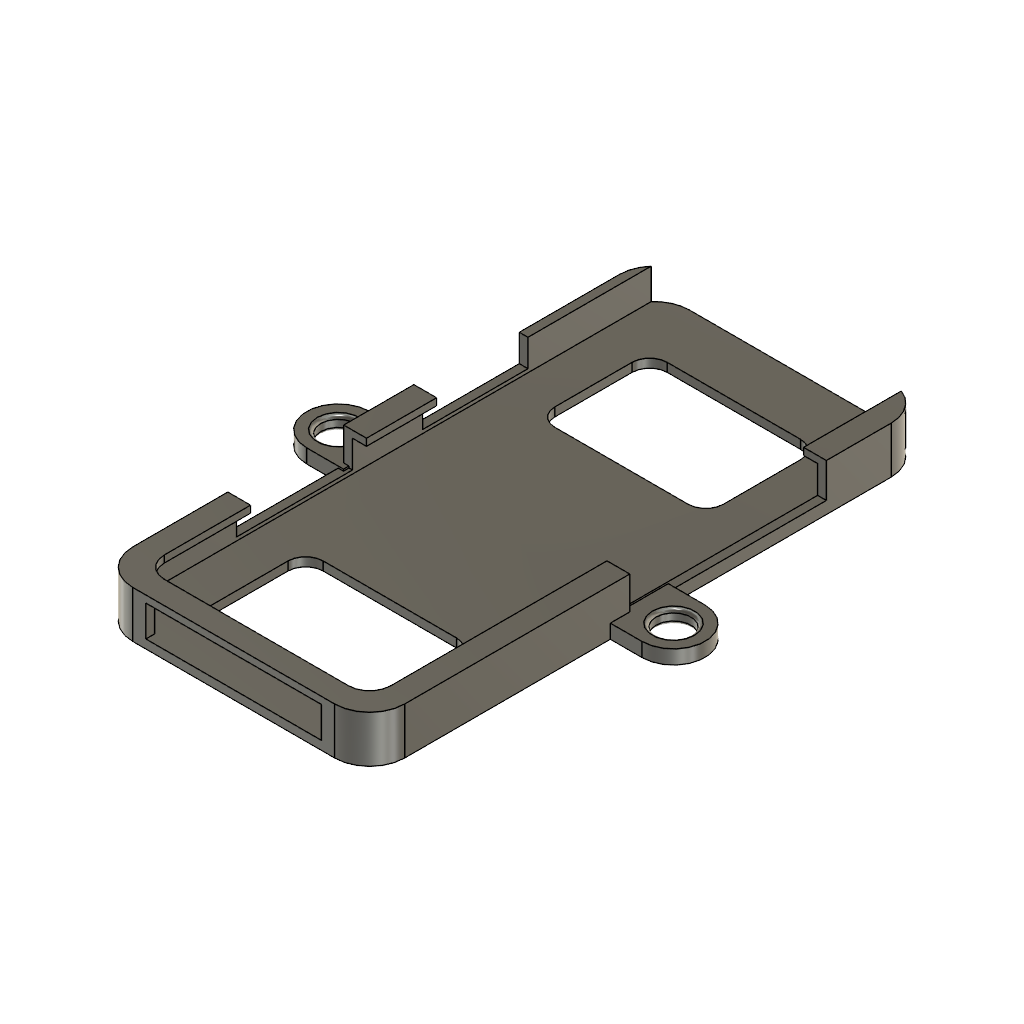
iphone holder 16 pro (Autodesk Fusion 360 design; units mm, degrees)
Autodesk Fusion 360 part; units mm, degrees
sketch "Outer" plane through (0, 0, 0) normal (0, 0, 1) x (1, 0, 0)
  line L0 (-28.75, -2.5) -> (28.75, -2.5)
  line L1 (38.75, 7.5) -> (38.75, 146.1)
  line L2 (28.75, 156.1) -> (-28.75, 156.1)
  line L3 (-38.75, 146.1) -> (-38.75, 7.5)
  arc A0 (28.75, -2.5) -> (38.75, 7.5) centre (28.75, 7.5) ccw
  arc A1 (38.75, 146.1) -> (28.75, 156.1) centre (28.75, 146.1) ccw
  arc A2 (-28.75, 156.1) -> (-38.75, 146.1) centre (-28.75, 146.1) ccw
  arc A3 (-38.75, 7.5) -> (-28.75, -2.5) centre (-28.75, 7.5) ccw
extrude "Shell" add sketch "Outer" along normal blind 13.35
sketch "Pocket" plane through (0, 0, 0) normal (0, 0, 1) x (1, 0, 0)
  line L0 (-28.25, 0) -> (28.25, 0)
  line L1 (36.25, 8) -> (36.25, 168.1)
  line L2 (28.25, 176.1) -> (-28.25, 176.1)
  line L3 (-36.25, 168.1) -> (-36.25, 8)
  arc A0 (28.25, 0) -> (36.25, 8) centre (28.25, 8) ccw
  arc A1 (36.25, 168.1) -> (28.25, 176.1) centre (28.25, 168.1) ccw
  arc A2 (-28.25, 176.1) -> (-36.25, 168.1) centre (-28.25, 168.1) ccw
  arc A3 (-36.25, 8) -> (-28.25, 0) centre (-28.25, 8) ccw
extrude "Pocket (1)" cut sketch "Pocket" along normal blind 8.85 from surface at 2.5
sketch "LipWindow" plane through (0, 0, 0) normal (0, 0, 1) x (1, 0, 0)
  line L0 (-26.25, 4) -> (26.25, 4)
  line L1 (32.25, 10) -> (32.25, 170.1)
  line L2 (26.25, 176.1) -> (-26.25, 176.1)
  line L3 (-32.25, 170.1) -> (-32.25, 10)
  arc A0 (26.25, 4) -> (32.25, 10) centre (26.25, 10) ccw
  arc A1 (32.25, 170.1) -> (26.25, 176.1) centre (26.25, 170.1) ccw
  arc A2 (-26.25, 176.1) -> (-32.25, 170.1) centre (-26.25, 170.1) ccw
  arc A3 (-32.25, 10) -> (-26.25, 4) centre (-26.25, 10) ccw
extrude "LipWindow (1)" cut sketch "LipWindow" along normal blind 3.1 from surface at 11.25
sketch "CameraClear" plane through (0, 0, 0) normal (0, 0, 1) x (1, 0, 0)
  line L0 (-43.75, 94.6) -> (-31.25, 94.6)
  line L1 (-31.25, 94.6) -> (-31.25, 176.1)
  line L2 (-31.25, 176.1) -> (-43.75, 176.1)
  line L3 (-43.75, 176.1) -> (-43.75, 94.6)
extrude "CameraClear (1)" cut sketch "CameraClear" along normal blind 3.1 from surface at 11.25
sketch "BottomPort" plane through (0, 0, 0) normal (0, 0, 1) x (1, 0, 0)
  line L0 (-25, -7.5) -> (25, -7.5)
  line L1 (25, -7.5) -> (25, 1)
  line L2 (25, 1) -> (-25, 1)
  line L3 (-25, 1) -> (-25, -7.5)
extrude "BottomPort (1)" cut sketch "BottomPort" along normal blind 8.85 from surface at 2.5
sketch "VolSlot" plane through (0, 0, 0) normal (0, 0, 1) x (1, 0, 0)
  line L0 (31.25, 71.6) -> (43.75, 71.6)
  line L1 (43.75, 71.6) -> (43.75, 127.6)
  line L2 (43.75, 127.6) -> (31.25, 127.6)
  line L3 (31.25, 127.6) -> (31.25, 71.6)
extrude "VolSlot (1)" cut sketch "VolSlot" along normal blind 10.85 from surface at 3.5
sketch "SideBtnSlot" plane through (0, 0, 0) normal (0, 0, 1) x (1, 0, 0)
  line L0 (-43.75, 87.6) -> (-31.25, 87.6)
  line L1 (-31.25, 87.6) -> (-31.25, 117.6)
  line L2 (-31.25, 117.6) -> (-43.75, 117.6)
  line L3 (-43.75, 117.6) -> (-43.75, 87.6)
extrude "SideBtnSlot (1)" cut sketch "SideBtnSlot" along normal blind 10.85 from surface at 3.5
sketch "CamCtrlSlot" plane through (0, 0, 0) normal (0, 0, 1) x (1, 0, 0)
  line L0 (-43.75, 34.6) -> (-31.25, 34.6)
  line L1 (-31.25, 34.6) -> (-31.25, 67.6)
  line L2 (-31.25, 67.6) -> (-43.75, 67.6)
  line L3 (-43.75, 67.6) -> (-43.75, 34.6)
extrude "CamCtrlSlot (1)" cut sketch "CamCtrlSlot" along normal blind 10.85 from surface at 3.5
sketch "WinBottom" plane through (0, 0, 0) normal (0, 0, 1) x (1, 0, 0)
  line L0 (-19, 10) -> (19, 10)
  line L1 (24, 15) -> (24, 37)
  line L2 (19, 42) -> (-19, 42)
  line L3 (-24, 37) -> (-24, 15)
  arc A0 (19, 10) -> (24, 15) centre (19, 15) ccw
  arc A1 (24, 37) -> (19, 42) centre (19, 37) ccw
  arc A2 (-19, 42) -> (-24, 37) centre (-19, 37) ccw
  arc A3 (-24, 15) -> (-19, 10) centre (-19, 15) ccw
extrude "WinBottom (1)" cut sketch "WinBottom" along normal blind 2.7 from surface at -0.1
sketch "WinTop" plane through (0, 0, 0) normal (0, 0, 1) x (1, 0, 0)
  line L0 (-19, 108) -> (19, 108)
  line L1 (24, 113) -> (24, 135)
  line L2 (19, 140) -> (-19, 140)
  line L3 (-24, 135) -> (-24, 113)
  arc A0 (19, 108) -> (24, 113) centre (19, 113) ccw
  arc A1 (24, 135) -> (19, 140) centre (19, 135) ccw
  arc A2 (-19, 140) -> (-24, 135) centre (-19, 135) ccw
  arc A3 (-24, 113) -> (-19, 108) centre (-19, 113) ccw
extrude "WinTop (1)" cut sketch "WinTop" along normal blind 2.7 from surface at -0.1
sketch "SocketBoss" plane through (0, 0, 0) normal (0, 0, 1) x (1, 0, 0)
  circle A0 centre (0, 75.05) radius 28
extrude "SocketBoss (1)" [suppressed]
sketch "SocketRecess" plane through (0, 0, 0) normal (0, 0, 1) x (1, 0, 0)
  circle A0 centre (0, 75.05) radius 23.5
extrude "SocketRecess (1)" [suppressed]
sketch "SocketLugs" plane through (0, 0, 0) normal (0, 0, 1) x (1, 0, 0)
  line L0 (6.8404, 93.8439) -> (8.2085, 97.6026)
  line L1 (-8.2085, 97.6026) -> (-6.8404, 93.8439)
  arc A0 (8.2085, 97.6026) -> (-8.2085, 97.6026) centre (0, 75.05) ccw
  arc A1 (6.8404, 93.8439) -> (-6.8404, 93.8439) centre (0, 75.05) ccw
  line L2 (-19.6962, 71.577) -> (-23.6354, 70.8824)
  line L3 (-15.4269, 56.6649) -> (-12.8558, 59.7291)
  arc A2 (-23.6354, 70.8824) -> (-15.4269, 56.6649) centre (0, 75.05) ccw
  arc A3 (-19.6962, 71.577) -> (-12.8558, 59.7291) centre (0, 75.05) ccw
  line L4 (12.8558, 59.7291) -> (15.4269, 56.6649)
  line L5 (23.6354, 70.8824) -> (19.6962, 71.577)
  arc A4 (15.4269, 56.6649) -> (23.6354, 70.8824) centre (0, 75.05) ccw
  arc A5 (12.8558, 59.7291) -> (19.6962, 71.577) centre (0, 75.05) ccw
extrude "SocketLugs (1)" [suppressed]
sketch "PinHole" plane through (0, 0, 0) normal (1, 0, 0) x (0, 0, -1)
  circle A0 centre (-6.925, 151.8) radius 1.65
extrude "PinHole (1)" cut sketch "PinHole" along normal mid plane 50
sketch "DiscFlange" plane through (0, 0, 0) normal (0, 0, 1) x (1, 0, 0)
  circle A0 centre (0, 75.05) radius 30
extrude "DiscFlange (1)" [suppressed]
sketch "DiscPost" plane through (0, 0, 0) normal (0, 0, 1) x (1, 0, 0)
  circle A0 centre (0, 75.05) radius 18.8
extrude "DiscPost (1)" [suppressed]
sketch "DiscLugs" plane through (0, 0, 0) normal (0, 0, 1) x (1, 0, 0)
  line L0 (6.5581, 92.1345) -> (7.9916, 95.8688)
  line L1 (-5.7717, 96.5901) -> (-4.7364, 92.7264)
  arc A0 (7.9916, 95.8688) -> (-5.7717, 96.5901) centre (0, 75.05) ccw
  arc A1 (6.5581, 92.1345) -> (-4.7364, 92.7264) centre (0, 75.05) ccw
  line L2 (-18.0747, 72.1872) -> (-22.0254, 71.5615)
  line L3 (-15.7685, 59.2815) -> (-12.9401, 62.1099)
  arc A2 (-22.0254, 71.5615) -> (-15.7685, 59.2815) centre (0, 75.05) ccw
  arc A3 (-18.0747, 72.1872) -> (-12.9401, 62.1099) centre (0, 75.05) ccw
  line L4 (11.5166, 60.8282) -> (14.0338, 57.7196)
  line L5 (21.5401, 69.2783) -> (17.6764, 70.3136)
  arc A4 (14.0338, 57.7196) -> (21.5401, 69.2783) centre (0, 75.05) ccw
  arc A5 (11.5166, 60.8282) -> (17.6764, 70.3136) centre (0, 75.05) ccw
extrude "DiscLugs (1)" [suppressed]
sketch "DiscStops" plane through (0, 0, 0) normal (0, 0, 1) x (1, 0, 0)
  line L0 (8.308, 91.3554) -> (10.124, 94.9194)
  line L1 (7.8096, 95.9378) -> (6.4088, 92.1911)
  arc A0 (10.124, 94.9194) -> (7.8096, 95.9378) centre (0, 75.05) ccw
  arc A1 (8.308, 91.3554) -> (6.4088, 92.1911) centre (0, 75.05) ccw
  line L2 (-18.2749, 74.0923) -> (-22.2694, 73.8829)
  line L3 (-21.9942, 71.3694) -> (-18.049, 72.0296)
  arc A2 (-22.2694, 73.8829) -> (-21.9942, 71.3694) centre (0, 75.05) ccw
  arc A3 (-18.2749, 74.0923) -> (-18.049, 72.0296) centre (0, 75.05) ccw
  line L4 (9.9669, 59.7023) -> (12.1455, 56.3476)
  line L5 (14.1845, 57.8428) -> (11.6402, 60.9293)
  arc A4 (12.1455, 56.3476) -> (14.1845, 57.8428) centre (0, 75.05) ccw
  arc A5 (9.9669, 59.7023) -> (11.6402, 60.9293) centre (0, 75.05) ccw
extrude "DiscStops (1)" [suppressed]
fillet "DiscFlangeFillet" [suppressed]
fillet "DiscHeadFillet" [suppressed]
sketch "StrapTabs" plane through (0, 0, 0) normal (0, 0, 1) x (1, 0, 0)
  line L0 (37.25, 66.05) -> (47.75, 66.05)
  line L1 (37.25, 84.05) -> (47.75, 84.05)
  line L2 (37.25, 66.05) -> (37.25, 84.05)
  arc A0 (47.75, 66.05) -> (47.75, 84.05) centre (47.75, 75.05) ccw
  line L3 (-37.25, 66.05) -> (-47.75, 66.05)
  line L4 (-37.25, 84.05) -> (-47.75, 84.05)
  line L5 (-37.25, 66.05) -> (-37.25, 84.05)
  arc A1 (-47.75, 84.05) -> (-47.75, 66.05) centre (-47.75, 75.05) ccw
extrude "StrapTabs (1)" add sketch "StrapTabs" along normal blind 4
sketch "StrapHoles" plane through (0, 0, 0) normal (0, 0, 1) x (1, 0, 0)
  circle A0 centre (47.75, 75.05) radius 5
  circle A1 centre (-47.75, 75.05) radius 5
extrude "StrapHoles (1)" cut sketch "StrapHoles" along normal blind 6 from surface at -1
fillet "StrapHoleFillet" radius 1 4 edges at (43.0884, 73.2419, 0) (43.0884, 76.8581, 4) (-52.4116, 76.8581, 4) (-52.4116, 73.2419, 0)
named bodies: "Holder", "InnerDisc"
